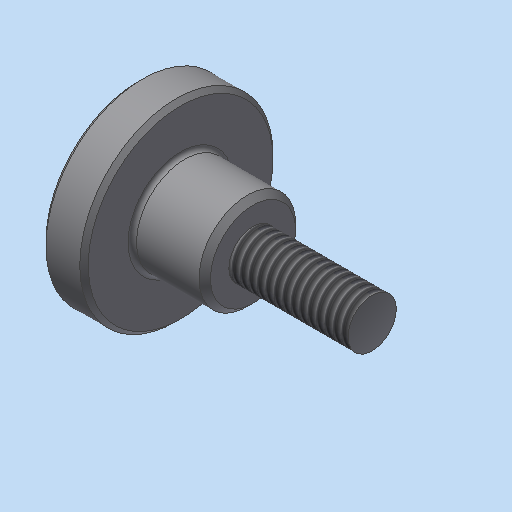
# Autodesk Inventor part: MM0948AN002_G02_101
Saved by Autodesk Inventor 2023.3 (Build 273359000, 359)
## iProperties
Created: 2017-02-08
Part Number: MM0948AN002_G02_101
Catalog Web Link: www.cadenas.de
Description: =<RBPARTNOTITLE2>
Vendor: Norelem
Document SubType Name: Modeling
Designer: psAdmin
Manufacturer: NORELEM
Mass: 9.8742 g
Surface Area: 8.21048 cm^2
Volume: 1.12207 cm^3
Density: 8.8 g/cm^3
Material: Generisch
Appearance: Vorgabe
Category: PARTsolutions
Company: NORELEM
PSOL_IDENT_0: {$CADENAS_DATA\23d-libs\norelem\data\06000\06090.prj},166 {VTYP=3D},{NB=06090-042X20},{LINA=06090-04
PSOL_IDENT_1: 2X20},{NN=06090},{DATE=03.02.2017 06:37:05},{GEOMDATE=02.02.2017 09:17:18},{VERSION=},{LINEID=180},{
PSOL_IDENT_2: LINESUBID=-1},{WBVAR=}  {NB=06090-042X20},{LINA=06090-042X20},{KT=DUMMY},{BESTKIPP=K0140.042X20},{BE
PSOL_IDENT_3: STKIPPUSA=K0140.042X20},{BESTKIPPUSAOLD=06090-042X20},{BEST=06090-042X20},{BESTNOVONOX=80-24-3},{BES
PSOL_IDENT_4: TKIPPOLD=06090-042X20},{FILTER=KIPP,NORELEM,KIPP_USA,NOVONOX},{WS=Edelstahl},{D1=M 4},{D2=16},{D3=8}
PSOL_IDENT_5: ,{L=20},{H=9.5},{K=3.5},{BS=Infotext},{BM=Bemerkung},{TYP=1},{NDM=4.000},{NDM1=0.0000},{TYP1=1},{XA=
PSOL_IDENT_6: 1.000},{XB=2.900},{XC=1.80}
NN: 06090
NT: Knurled screws high steel and stainless steel DIN 464
NB: 06090-042X20
NBSYN: $BEST.
LINA: 06090-042X20
BEST: 06090-042X20
WS: Stainless steel
D1: M 4
D2: 16
D3: 8
L: 20
H: 9.5
K: 3.5
BS: Infotext
BM: Comment
SUPPLIER: NORELEM
ARTICLENO: 06090-042X20
BOMINFO: 06090-042X20
CREATOR: CADENAS GmbH
RBPARTMADEOF: 06090-042X10
RBDRAWINGMISSINGSPEC: --
AnP_Kategorie: 2
RBPARTNOTITLE2: Raendelschraube hoch DIN464
RBGBREMARKSINDEX: E
RBSURFACE: --
RBPARTNOTITLE1: knurled screw hoch DIN464
RBSURFACE2: --
AnP_Material: =<Material>
RBMATERIAL: =<Material>
RBMATNO: =<Part Number>
RBPARTNO: SIEHE MNR
Title: 06090-042X20
Author: Cadenas PARTsolutions
Comments: =<RBSURFACE2>
Keywords: =<RBPARTMADEOF>
Revision Number: 01
Autodesk Inventor part; units mm, degrees
sketch "Skizze_2" plane through (0, 0, 0) normal (0, 0, 1) x (1, 0, 0)
  line L0 (29.5, 0) -> (0, 0)
  line L1 (0, 0) -> (0, 7.65)
  line L2 (0, 7.65) -> (0.35, 8)
  line L3 (0.35, 8) -> (3.15, 8)
  line L4 (3.15, 8) -> (3.5, 7.65)
  line L5 (3.5, 7.65) -> (3.5, 4.35)
  arc A0 (3.5, 4.35) -> (3.85, 4) centre (3.85, 4.35) ccw
  line L6 (3.85, 4) -> (9.025, 4)
  line L7 (9.025, 4) -> (9.5, 3.525)
  line L8 (9.5, 3.525) -> (9.5, 2)
  line L9 (9.5, 2) -> (29.3745, 2)
  arc A1 (29.5, 0) -> (29.3745, 2) centre (13.5, 0) ccw
  line L10 (29.5, 0) -> (0, 0)
  constraints: 22 end point, 4 point on circle, 2 centre point
revolve "Revolution1" add sketch "Skizze_2" angle 360 about axis through (29.5, 0, 0) along (-1, 0, 0)
thread "Thread1" size "M4x0.7" class "6g" standard "ISO Metric profile" full length
ref_plane "Rp_XY" through (9.5, 0, 0) normal (1, 0, 0) x (0, 0, -1)
ref_plane "Rp_YZ" through (9.5, 0, 0) normal (0, 0, -1) x (0, 1, 0)
ref_plane "Rp_ZX" through (9.5, 0, 0) normal (0, 1, 0) x (1, 0, 0)
move faces "Verschieben1" translate (-10, 0, 0) faces at (29.4752, 0.7529, -0.4761)
body "Solid1"
